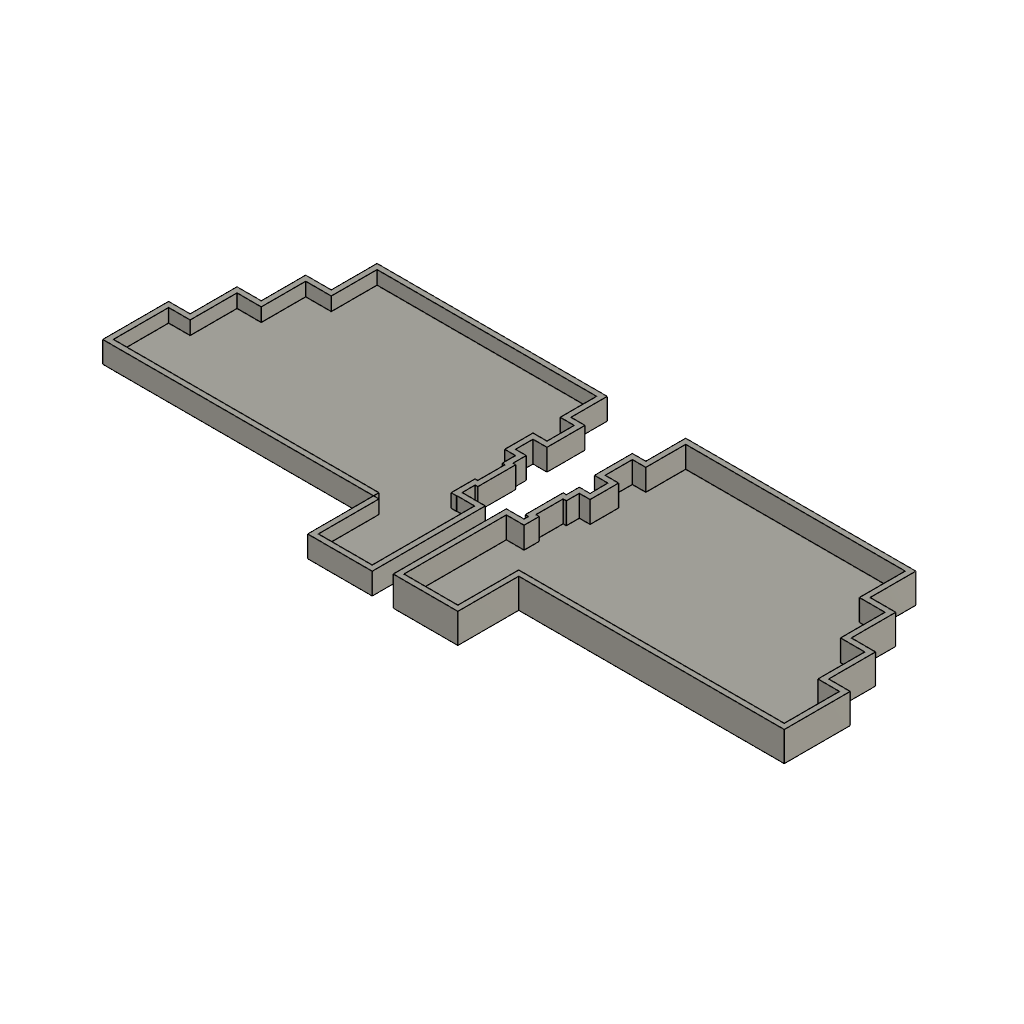
Jarned V2 (Autodesk Fusion 360 design; units mm, degrees)
part number: 2026-11-08-21-23-21-897
Autodesk Fusion 360 part; units mm, degrees
sketch "Sketch1" plane through (0, 0, 0) normal (0, 0, 1) x (1, 0, 0)
  line L0 (0, -12.5) -> (98.6, -12.5)
  line L1 (98.6, -12.5) -> (98.6, 0.9)
  line L2 (98.6, 0.9) -> (100, 0.9)
  line L3 (100, 0.9) -> (100, 2.9)
  line L4 (100, 2.9) -> (112, 2.9)
  line L5 (112, 2.9) -> (112, 9.8)
  line L6 (112, 9.8) -> (113, 9.8)
  line L7 (113, 9.8) -> (113, 19.9)
  line L8 (113, 19.9) -> (112, 19.9)
  line L9 (112, 19.9) -> (112, 24.8)
  line L10 (112, 24.8) -> (108, 24.8)
  line L11 (108, 24.8) -> (108, 35.3)
  line L12 (108, 35.3) -> (113.2, 35.3)
  line L13 (113.2, 35.3) -> (113.2, 45.4)
  line L14 (113.2, 45.4) -> (108, 45.4)
  line L15 (108, 45.4) -> (108, 58.9)
  line L16 (108, 58.9) -> (26.5, 58.9)
  line L17 (26.5, 58.9) -> (26.5, 41.9)
  line L18 (26.5, 41.9) -> (17, 41.9)
  line L19 (17, 41.9) -> (17, 25.4)
  line L20 (17, 25.4) -> (8, 25.4)
  line L21 (8, 25.4) -> (8, 8)
  line L22 (8, 8) -> (0, 8)
  line L23 (0, 8) -> (0, -12.5)
  line L24 (15, 27.4) -> (6, 27.4)
  line L25 (6, 27.4) -> (6, 10)
  line L26 (6, 10) -> (-2, 10)
  line L27 (-2, 10) -> (-2, -14.5)
  line L28 (-2, -14.5) -> (100.6, -14.5)
  line L29 (100.6, -14.5) -> (100.6, -1.1)
  line L30 (100.6, -1.1) -> (102, -1.1)
  line L31 (102, -1.1) -> (102, 0.9)
  line L32 (102, 0.9) -> (114, 0.9)
  line L33 (114, 0.9) -> (114, 7.8)
  line L34 (114, 7.8) -> (115, 7.8)
  line L35 (115, 7.8) -> (115, 21.9)
  line L36 (115, 21.9) -> (114, 21.9)
  line L37 (114, 21.9) -> (114, 26.8)
  line L38 (114, 26.8) -> (110, 26.8)
  line L39 (110, 26.8) -> (110, 33.3)
  line L40 (110, 33.3) -> (115.2, 33.3)
  line L41 (115.2, 33.3) -> (115.2, 47.4)
  line L42 (115.2, 47.4) -> (110, 47.4)
  line L43 (110, 47.4) -> (110, 60.9)
  line L44 (110, 60.9) -> (24.5, 60.9)
  line L45 (24.5, 60.9) -> (24.5, 43.9)
  line L46 (24.5, 43.9) -> (15, 43.9)
  line L47 (15, 43.9) -> (15, 27.4)
  dimension "d1" = 98.6
  dimension "d2" = 13.4
  dimension "d3" = 2
  dimension "d4" = 12
  dimension "d5" = 6.9
  dimension "d6" = 10.1
  dimension "d7" = 4.9
  dimension "d8" = 4
  dimension "d9" = 10.5
  dimension "d10" = 5.2
  dimension "d11" = 10.1
  dimension "d12" = 13.5
  dimension "d13" = 81.5
  dimension "d14" = 17
  dimension "d15" = 9.5
  dimension "d16" = 16.5
  dimension "d17" = 9
  dimension "d18" = 17.4
  dimension "d19" = 2
  constraint horizontal L0
  constraint perpendicular L0 L1
  constraint perpendicular L1 L2
  constraint perpendicular L2 L3
  constraint perpendicular L3 L4
  constraint perpendicular L4 L5
  constraint perpendicular L5 L6
  constraint perpendicular L6 L7
  constraint perpendicular L7 L8
  constraint perpendicular L8 L9
  constraint perpendicular L9 L10
  constraint perpendicular L10 L11
  constraint perpendicular L11 L12
  constraint perpendicular L12 L13
  constraint perpendicular L13 L14
  constraint perpendicular L14 L15
  constraint perpendicular L15 L16
  constraint perpendicular L16 L17
  constraint perpendicular L17 L18
  constraint perpendicular L18 L19
  constraint perpendicular L19 L20
  constraint perpendicular L20 L21
  constraint perpendicular L21 L22
  constraint perpendicular L0 L23
  measures "d1" distance of L0.start L0.end
  measures "d2" distance of L0.end L1.end
  measures "d3" distance of L2.end L3.end
  measures "d4" distance of L3.end L4.end
  measures "d5" distance of L4.end L5.end
  measures "d6" distance of L6.end L7.end
  measures "d7" distance of L8.end L9.end
  measures "d8" distance of L9.end L10.end
  measures "d9" distance of L10.end L11.end
  measures "d10" distance of L11.end L12.end
  measures "d11" distance of L12.end L13.end
  measures "d12" distance of L14.end L15.end
  measures "d13" distance of L15.end L16.end
  measures "d14" distance of L16.end L17.end
  measures "d15" distance of L17.end L18.end
  measures "d16" distance of L18.end L19.end
  measures "d17" distance of L19.end L20.end
  measures "d18" distance of L20.end L21.end
extrude "Extrude1" add sketch "Sketch1" along normal blind 6 makes body 1
sketch "Sketch2" plane through (0, 0, 0) normal (0, 0, 1) x (1, 0, 0)
  line L0 (26.5, 58.9) -> (108, 58.9)
  line L1 (108, 58.9) -> (108, 45.4)
  line L2 (108, 45.4) -> (113.2, 45.4)
  line L3 (113.2, 45.4) -> (113.2, 35.3)
  line L4 (113.2, 35.3) -> (108, 35.3)
  line L5 (108, 35.3) -> (108, 24.8)
  line L6 (108, 24.8) -> (112, 24.8)
  line L7 (112, 24.8) -> (112, 19.9)
  line L8 (112, 19.9) -> (113, 19.9)
  line L9 (113, 19.9) -> (113, 9.8)
  line L10 (113, 9.8) -> (112, 9.8)
  line L11 (112, 9.8) -> (112, 2.9)
  line L12 (112, 2.9) -> (100, 2.9)
  line L13 (100, 2.9) -> (100, 0.9)
  line L14 (100, 0.9) -> (98.6, 0.9)
  line L15 (98.6, 0.9) -> (98.6, -12.5)
  line L16 (98.6, -12.5) -> (0, -12.5)
  line L17 (0, -12.5) -> (0, 8)
  line L18 (0, 8) -> (8, 8)
  line L19 (8, 8) -> (8, 25.4)
  line L20 (8, 25.4) -> (17, 25.4)
  line L21 (17, 25.4) -> (17, 41.9)
  line L22 (17, 41.9) -> (26.5, 41.9)
  line L23 (26.5, 41.9) -> (26.5, 58.9)
  constraint horizontal L0
  constraint perpendicular L0 L1
  constraint perpendicular L1 L2
  constraint perpendicular L2 L3
  constraint perpendicular L3 L4
  constraint perpendicular L4 L5
  constraint perpendicular L5 L6
  constraint perpendicular L6 L7
  constraint perpendicular L7 L8
  constraint perpendicular L8 L9
  constraint perpendicular L9 L10
  constraint perpendicular L10 L11
  constraint perpendicular L11 L12
  constraint perpendicular L12 L13
  constraint perpendicular L13 L14
  constraint perpendicular L12 L15
  constraint perpendicular L13 L16
  constraint perpendicular L12 L17
  constraint perpendicular L17 L18
  constraint perpendicular L18 L19
  constraint perpendicular L19 L20
  constraint perpendicular L20 L21
  constraint perpendicular L21 L22
  constraint perpendicular L0 L23
extrude "Extrude2" add sketch "Sketch2" along normal blind 3 bodies 1
sketch "Sketch3" plane through (0, 0, 0) normal (0, 0, 1) x (1, 0, 0)
  line L0 (140, 60) -> (221.5, 60)
  line L1 (221.5, 60) -> (221.5, 43)
  line L2 (221.5, 43) -> (231, 43)
  line L3 (231, 43) -> (231, 26.5)
  line L4 (231, 26.5) -> (240, 26.5)
  line L5 (240, 26.5) -> (240, 9.1)
  line L6 (240, 9.1) -> (248, 9.1)
  line L7 (248, 9.1) -> (248, -11.4)
  line L8 (248, -11.4) -> (149.4, -11.4)
  line L9 (149.4, -11.4) -> (149.4, 2)
  line L10 (149.4, 2) -> (148, 2)
  line L11 (148, 2) -> (148, 4)
  line L12 (148, 4) -> (136, 4)
  line L13 (136, 4) -> (136, 9.6)
  line L14 (136, 9.6) -> (134.8, 9.6)
  line L15 (134.8, 9.6) -> (134.8, 19.7)
  line L16 (134.8, 19.7) -> (136, 19.7)
  line L17 (136, 19.7) -> (136, 24.5)
  line L18 (136, 24.5) -> (140, 24.5)
  line L19 (140, 24.5) -> (140, 35.1)
  line L20 (140, 35.1) -> (135, 35.1)
  line L21 (135, 35.1) -> (135, 45.2)
  line L22 (135, 45.2) -> (140, 45.2)
  line L23 (140, 45.2) -> (140, 60)
  line L24 (223.5, 45) -> (233, 45)
  line L25 (233, 45) -> (233, 28.5)
  line L26 (233, 28.5) -> (242, 28.5)
  line L27 (242, 28.5) -> (242, 11.1)
  line L28 (242, 11.1) -> (250, 11.1)
  line L29 (250, 11.1) -> (250, -13.4)
  line L30 (250, -13.4) -> (147.4, -13.4)
  line L31 (147.4, -13.4) -> (147.4, 0)
  line L32 (147.4, 0) -> (146, 0)
  line L33 (146, 0) -> (146, 2)
  line L34 (146, 2) -> (134, 2)
  line L35 (134, 2) -> (134, 7.6)
  line L36 (134, 7.6) -> (132.8, 7.6)
  line L37 (132.8, 7.6) -> (132.8, 21.7)
  line L38 (132.8, 21.7) -> (134, 21.7)
  line L39 (134, 21.7) -> (134, 26.5)
  line L40 (134, 26.5) -> (138, 26.5)
  line L41 (138, 26.5) -> (138, 33.1)
  line L42 (138, 33.1) -> (133, 33.1)
  line L43 (133, 33.1) -> (133, 47.2)
  line L44 (133, 47.2) -> (138, 47.2)
  line L45 (138, 47.2) -> (138, 62)
  line L46 (138, 62) -> (223.5, 62)
  line L47 (223.5, 62) -> (223.5, 45)
  dimension "d24" = 81.5
  dimension "d25" = 17
  dimension "d26" = 9.5
  dimension "d27" = 16.5
  dimension "d28" = 9
  dimension "d29" = 17.4
  dimension "d30" = 8
  dimension "d31" = 20.5
  dimension "d32" = 98.6
  dimension "d33" = 13.4
  dimension "d34" = 12
  dimension "d35" = 5.6
  dimension "d36" = 1.2
  dimension "d37" = 10.1
  dimension "d38" = 4.8
  dimension "d39" = 4
  dimension "d40" = 10.6
  dimension "d41" = 5
  dimension "d42" = 10.1
  dimension "d43" = -2
  constraint horizontal L0
  constraint perpendicular L0 L1
  constraint perpendicular L1 L2
  constraint perpendicular L2 L3
  constraint perpendicular L3 L4
  constraint perpendicular L4 L5
  constraint perpendicular L5 L6
  constraint perpendicular L6 L7
  constraint perpendicular L7 L8
  constraint perpendicular L8 L9
  constraint perpendicular L9 L10
  constraint perpendicular L10 L11
  constraint perpendicular L11 L12
  constraint perpendicular L12 L13
  constraint perpendicular L13 L14
  constraint perpendicular L14 L15
  constraint perpendicular L15 L16
  constraint perpendicular L16 L17
  constraint perpendicular L17 L18
  constraint perpendicular L18 L19
  constraint perpendicular L19 L20
  constraint perpendicular L20 L21
  constraint perpendicular L21 L22
  constraint perpendicular L0 L23
  measures "d24" distance of L0.start L0.end
  measures "d25" distance of L0.end L1.end
  measures "d26" distance of L1.end L2.end
  measures "d27" distance of L2.end L3.end
  measures "d28" distance of L3.end L4.end
  measures "d29" distance of L4.end L5.end
  measures "d30" distance of L5.end L6.end
  measures "d31" distance of L6.end L7.end
  measures "d32" distance of L7.end L8.end
  measures "d33" distance of L8.end L9.end
  measures "d34" distance of L11.end L12.end
  measures "d35" distance of L12.end L13.end
  measures "d36" distance of L13.end L14.end
  measures "d37" distance of L14.end L15.end
  measures "d38" distance of L16.end L17.end
  measures "d39" distance of L17.end L18.end
  measures "d40" distance of L18.end L19.end
  measures "d41" distance of L19.end L20.end
  measures "d42" distance of L20.end L21.end
extrude "Extrude3" add sketch "Sketch3" along normal blind 6 separate body makes body 2
extrude "Extrude4" add 1 faces at (32.8667, -13.8333, 6) along direction (0, 0, 1) blind 2 on bodies 1 bodies 1
extrude "Extrude5" add 1 faces at (182.2667, -12.7333, 6) along direction (0, 0, 1) blind 2 on bodies 2 bodies 2
sketch "Sketch4" plane through (0, 0, 0) normal (0, 0, 1) x (1, 0, 0)
  line L0 (140, 60) -> (221.5, 60)
  line L1 (221.5, 60) -> (221.5, 43)
  line L2 (140, 45.216) -> (140, 60)
  line L3 (221.5, 43) -> (231, 43)
  line L4 (231, 43) -> (231, 26.5)
  line L5 (231, 26.5) -> (240, 26.5)
  line L6 (240, 26.5) -> (240, 9.1)
  line L7 (240, 9.1) -> (248, 9.1)
  line L8 (248, 9.1) -> (248, -11.4)
  line L9 (248, -11.4) -> (240, -11.4)
  line L10 (140, 45.216) -> (135, 45.216)
  line L11 (135, 45.216) -> (135, 35.1)
  line L12 (135, 35.1) -> (140, 35.1)
  line L13 (140, 24.5) -> (136, 24.5)
  line L14 (136, 24.5) -> (136, 19.7)
  line L15 (136, 19.7) -> (134.8, 19.7)
  line L16 (134.8, 19.7) -> (134.8, 9.6)
  line L17 (134.8, 9.6) -> (136, 9.6)
  line L18 (148, 4) -> (136, 4)
  line L19 (136, 4) -> (136, 9.6)
  line L20 (149.4, 2) -> (148, 2)
  line L21 (148, 2) -> (148, 4)
  line L22 (240, -11.4) -> (149.4, -11.4)
  line L23 (149.4, -11.4) -> (149.4, 2)
  line L24 (149.4, 2) -> (148, 2)
  line L25 (148, 2) -> (148, 4)
  line L26 (240, 9.6) -> (240, 9.1)
  line L27 (221.5, 43.5352) -> (231, 43.5352)
  line L28 (231, 43.5352) -> (231, 26.5)
  line L29 (140, 24.5) -> (140, 35.1)
  constraint horizontal L0
  constraint vertical L1
  constraint vertical L2
  constraint horizontal L3
  constraint vertical L4
  constraint horizontal L5
  constraint vertical L6
  constraint horizontal L7
  constraint vertical L8
  constraint horizontal L9
  constraint horizontal L10
  constraint vertical L11
  constraint horizontal L12
  constraint horizontal L13
  constraint vertical L14
  constraint horizontal L15
  constraint vertical L16
  constraint horizontal L17
  constraint horizontal L18
  constraint vertical L19
  constraint horizontal L20
  constraint vertical L21
  constraint horizontal L22
  constraint vertical L23
  constraint horizontal L24
  constraint vertical L25
  constraint vertical L26
  constraint vertical L29
  constraint horizontal L27
  constraint vertical L28
  constraint coincident L1 L27.start
extrude "Extrude6" add sketch "Sketch4" against normal blind 3 separate body contours L0 L1 L2 L3 L4 L5 L6 L7 L8 L9 L10 L11 L12 L13 L14 L15 L16 L17 L18 L19 L20 L21 L22 L23 L24 L25 L26 L28 L29 makes body 3
sketch "Sketch5" plane through (0, 0, 0) normal (0, 0, 1) x (1, 0, 0)
sketch "Sketch6" plane through (0, 0, 8) normal (0, 0, 1) x (-1, 0, 0)
  line L0 (0, 12.5) -> (0, -8)
  line L1 (0, -8) -> (-8, -8)
  line L2 (-8, -8) -> (-8, -25.4)
  line L3 (-8, -25.4) -> (-17, -25.4)
  line L4 (-17, -25.4) -> (-17, -41.9)
  line L5 (-17, -41.9) -> (-26.5, -41.9)
  line L6 (-26.5, -41.9) -> (-26.5, -58.9)
  line L7 (-26.5, -58.9) -> (-108, -58.9)
  line L8 (-108, -58.9) -> (-108, -45.4)
  line L9 (-108, -45.4) -> (-113.2, -45.4)
  line L10 (-113.2, -45.4) -> (-113.2, -35.3)
  line L11 (-113.2, -35.3) -> (-108, -35.3)
  line L12 (-108, -35.3) -> (-108, -24.8)
  line L13 (-108, -24.8) -> (-112, -24.8)
  line L14 (-112, -24.8) -> (-112, -19.9)
  line L15 (-112, -19.9) -> (-113, -19.9)
  line L16 (-113, -19.9) -> (-113, -9.8)
  line L17 (-113, -9.8) -> (-112, -9.8)
  line L18 (-112, -9.8) -> (-112, -2.9)
  line L19 (-112, -2.9) -> (-100, -2.9)
  line L20 (-100, -2.9) -> (-100, -0.9)
  line L21 (-100, -0.9) -> (-98.6, -0.9)
  line L22 (-98.6, -0.9) -> (-98.6, 12.5)
  line L23 (-98.6, 12.5) -> (0, 12.5)
  line L24 (-15, -43.9) -> (-15, -27.4)
  line L25 (-15, -27.4) -> (-6, -27.4)
  line L26 (-6, -27.4) -> (-6, -10)
  line L27 (-6, -10) -> (2, -10)
  line L28 (2, -10) -> (2, 14.5)
  line L29 (2, 14.5) -> (-100.6, 14.5)
  line L30 (-100.6, 14.5) -> (-100.6, 1.1)
  line L31 (-100.6, 1.1) -> (-102, 1.1)
  line L32 (-102, 1.1) -> (-102, -0.9)
  line L33 (-102, -0.9) -> (-114, -0.9)
  line L34 (-114, -0.9) -> (-114, -7.8)
  line L35 (-114, -7.8) -> (-115, -7.8)
  line L36 (-115, -7.8) -> (-115, -21.9)
  line L37 (-115, -21.9) -> (-114, -21.9)
  line L38 (-114, -21.9) -> (-114, -26.8)
  line L39 (-114, -26.8) -> (-110, -26.8)
  line L40 (-110, -26.8) -> (-110, -33.3)
  line L41 (-110, -33.3) -> (-115.2, -33.3)
  line L42 (-115.2, -33.3) -> (-115.2, -47.4)
  line L43 (-115.2, -47.4) -> (-110, -47.4)
  line L44 (-110, -47.4) -> (-110, -60.9)
  line L45 (-110, -60.9) -> (-24.5, -60.9)
  line L46 (-24.5, -60.9) -> (-24.5, -43.9)
  line L47 (-24.5, -43.9) -> (-15, -43.9)
  line L48 (-98.6, 12.5) -> (-98.6, 14.5)
  line L49 (-98.6, 14.5) -> (-100.6, 14.5)
  line L50 (-100.6, 14.5) -> (-100.6, 1.1)
  line L51 (-102, 1.1) -> (-100.6, 1.1)
  line L52 (-102, 1.1) -> (-102, -0.9)
  line L53 (-102, -0.9) -> (-112, -0.9)
  line L54 (-112, -2.9) -> (-112, -0.9)
  line L55 (-112, -2.9) -> (-100, -2.9)
  line L56 (-100, -0.9) -> (-100, -2.9)
  line L57 (-100, -0.9) -> (-98.6, -0.9)
  line L58 (-98.6, -0.9) -> (-98.6, 12.5)
  constraint coincident L22.end L23.start
  constraint coincident L29 L48.end
  constraint perpendicular L29 L48
  constraint coincident L29.end L30.start
  constraint coincident L30.end L31.start
  constraint coincident L31.end L32.start
  constraint coincident L32.end L33.start
  constraint coincident L33 L53.end
  constraint coincident L18.end L19.start
  constraint coincident L19.end L20.start
  constraint coincident L20.end L21.start
  constraint coincident L21.end L22.start
extrude "Extrude7" cut sketch "Sketch6" against normal blind 6 contours L19 L20 L21 L22 L29 L30 L31 L32 L33 L48 L49 L50 L51 L52 L53 L54 L55 L56 L57 L58 bodies 1
extrude "Extrude8" add 1 faces at (99.2667, -4.9, 2) along direction (0, 0, 1) blind 1 on bodies 1 bodies 1
sketch "Sketch7" plane through (0, 0, 0) normal (0, 0, 1) x (1, 0, 0)
  line L0 (100.6, -37) -> (120.6, -37)
  line L1 (120.6, -37) -> (120.6, 1)
  line L2 (120.6, 1) -> (112, 1)
  line L3 (100.6, -37) -> (100.6, -14.5)
  line L4 (98.6, -39) -> (98.6, -14.5)
  line L5 (98.6, -39) -> (122.6, -39)
  line L6 (122.6, -39) -> (122.6, 3)
  line L7 (122.6, 3) -> (112, 3)
  line L8 (98.6, -14.5) -> (100.6, -14.5)
  line L9 (112, 3) -> (112, 1)
  dimension "d57" = 20
  dimension "d58" = -2
  constraint perpendicular L0 L1
  constraint perpendicular L1 L2
  constraint perpendicular L0 L3
  constraint perpendicular L3 L8
  constraint perpendicular L2 L9
  measures "d57" distance of L0.start L0.end
extrude "Extrude9" add sketch "Sketch7" along normal blind 8 bodies 1
sketch "Sketch8" plane through (0, 0, 0) normal (0, 0, 1) x (1, 0, 0)
  line L0 (114, 1) -> (114, 0.9)
  line L1 (114, 0.9) -> (102, 0.9)
  line L2 (102, 0.9) -> (102, -1.1)
  line L3 (102, -1.1) -> (100.6, -1.1)
  line L4 (100.6, -1.1) -> (100.6, -37)
  line L5 (100.6, -37) -> (120.6, -37)
  line L6 (120.6, -37) -> (120.6, 1)
  line L7 (120.6, 1) -> (114, 1)
  constraint vertical L0
  constraint perpendicular L0 L1
  constraint perpendicular L1 L2
  constraint perpendicular L2 L3
  constraint perpendicular L3 L4
  constraint perpendicular L4 L5
  constraint perpendicular L3 L6
extrude "Extrude10" add sketch "Sketch8" along normal blind 3 bodies 1
sketch "Sketch9" plane through (0, 0, 8) normal (0, 0, 1) x (-1, 0, 0)
  line L0 (-135, -45.2) -> (-140, -45.2)
  line L1 (-140, -45.2) -> (-140, -60)
  line L2 (-140, -60) -> (-221.5, -60)
  line L3 (-221.5, -60) -> (-221.5, -43)
  line L4 (-221.5, -43) -> (-231, -43)
  line L5 (-231, -43) -> (-231, -26.5)
  line L6 (-231, -26.5) -> (-240, -26.5)
  line L7 (-240, -26.5) -> (-240, -9.1)
  line L8 (-240, -9.1) -> (-248, -9.1)
  line L9 (-248, -9.1) -> (-248, 11.4)
  line L10 (-248, 11.4) -> (-149.4, 11.4)
  line L11 (-149.4, 11.4) -> (-149.4, -2)
  line L12 (-149.4, -2) -> (-148, -2)
  line L13 (-148, -2) -> (-148, -4)
  line L14 (-148, -4) -> (-136, -4)
  line L15 (-136, -4) -> (-136, -9.6)
  line L16 (-136, -9.6) -> (-134.8, -9.6)
  line L17 (-134.8, -9.6) -> (-134.8, -19.7)
  line L18 (-134.8, -19.7) -> (-136, -19.7)
  line L19 (-136, -19.7) -> (-136, -24.5)
  line L20 (-136, -24.5) -> (-140, -24.5)
  line L21 (-140, -24.5) -> (-140, -35.1)
  line L22 (-140, -35.1) -> (-135, -35.1)
  line L23 (-135, -35.1) -> (-135, -45.2)
  line L24 (-223.5, -62) -> (-138, -62)
  line L25 (-138, -62) -> (-138, -47.2)
  line L26 (-138, -47.2) -> (-133, -47.2)
  line L27 (-133, -47.2) -> (-133, -33.1)
  line L28 (-133, -33.1) -> (-138, -33.1)
  line L29 (-138, -33.1) -> (-138, -26.5)
  line L30 (-138, -26.5) -> (-134, -26.5)
  line L31 (-134, -26.5) -> (-134, -21.7)
  line L32 (-134, -21.7) -> (-132.8, -21.7)
  line L33 (-132.8, -21.7) -> (-132.8, -7.6)
  line L34 (-132.8, -7.6) -> (-134, -7.6)
  line L35 (-134, -7.6) -> (-134, -2)
  line L36 (-134, -2) -> (-146, -2)
  line L37 (-146, -2) -> (-146, 0)
  line L38 (-146, 0) -> (-147.4, 0)
  line L39 (-147.4, 0) -> (-147.4, 13.4)
  line L40 (-147.4, 13.4) -> (-250, 13.4)
  line L41 (-250, 13.4) -> (-250, -11.1)
  line L42 (-250, -11.1) -> (-242, -11.1)
  line L43 (-242, -11.1) -> (-242, -28.5)
  line L44 (-242, -28.5) -> (-233, -28.5)
  line L45 (-233, -28.5) -> (-233, -45)
  line L46 (-233, -45) -> (-223.5, -45)
  line L47 (-223.5, -45) -> (-223.5, -62)
  line L48 (-149.4, 11.4) -> (-149.4, 13.4)
  line L49 (-147.4, 13.4) -> (-149.4, 13.4)
  line L50 (-147.4, 13.4) -> (-147.4, 0)
  line L51 (-146, 0) -> (-147.4, 0)
  line L52 (-146, 0) -> (-146, -2)
  line L53 (-134, -4) -> (-136, -4)
  line L54 (-136, -4) -> (-148, -4)
  line L55 (-148, -2) -> (-148, -4)
  line L56 (-148, -2) -> (-149.4, -2)
  line L57 (-149.4, -2) -> (-149.4, 11.4)
  line L58 (-134, -4) -> (-134, -2)
  line L59 (-134, -2) -> (-146, -2)
  constraint coincident L10.end L11.start
  constraint coincident L40 L48.end
  constraint perpendicular L40 L48
  constraint coincident L39.end L40.start
  constraint coincident L38.end L39.start
  constraint coincident L37.end L38.start
  constraint coincident L36.end L37.start
  constraint coincident L35 L53.start
  constraint coincident L14.end L15.start
  constraint perpendicular L15 L53
  constraint coincident L13.end L14.start
  constraint coincident L12.end L13.start
  constraint coincident L11.end L12.start
  constraint coincident L35.end L36.start
extrude "Extrude11" cut sketch "Sketch9" against normal blind 11 contours L11 L12 L13 L14 L35 L36 L37 L38 L39 L40 L48 L49 L50 L51 L52 L53 L54 L55 L56 L57 L58 L59 bodies 2
extrude "Extrude12" add 1 faces at (215.8, -12.7333, 0) along direction (0, 0, -1) blind 3 on bodies 2 bodies 2 3
sketch "Sketch10" plane through (0, 0, 0) normal (0, 0, 1) x (1, 0, 0)
  line L0 (149.4, 4) -> (129.4, 4)
  line L1 (149.4, 4) -> (149.4, -34)
  line L2 (129.4, 4) -> (129.4, -34)
  line L3 (129.4, -34) -> (149.4, -34)
  dimension "d67" = 20
  dimension "d68" = 38
  constraint perpendicular L0 L1
  constraint perpendicular L0 L2
  measures "d67" distance of L0.start L0.end
  measures "d68" distance of L0.start L1.end
extrude "Extrude13" add sketch "Sketch10" along normal blind 3 bodies 2
extrude "Extrude14" add 1 faces at (136.0667, -14.4667, 0) along direction (0, 0, -1) blind 3 on bodies 2 bodies 2
extrude "Extrude15" cut 1 faces at (136.0667, -14.4667, 3) along direction (0, 0, -1) blind 3 on bodies 2 bodies 2
sketch "Sketch11" plane through (0, 0, 0) normal (0, 1, 0) x (1, 0, 0)
sketch "Sketch12" plane through (0, 0, 0) normal (0, 0, 1) x (1, 0, 0)
  line L0 (134, 4) -> (129.4, 4)
  line L1 (129.4, 4) -> (129.4, -34)
  line L2 (129.4, -34) -> (149.4, -34)
  line L3 (149.4, -34) -> (149.4, -13.4)
  line L4 (134, 6) -> (127.4, 6)
  line L5 (127.4, 6) -> (127.4, -36)
  line L6 (127.4, -36) -> (151.4, -36)
  line L7 (151.4, -36) -> (151.4, -13.4)
  line L8 (149.4, -13.4) -> (151.4, -13.4)
  line L9 (134, 6) -> (134, 4)
  dimension "d75" = 2
  constraint horizontal L0
  constraint perpendicular L0 L1
  constraint perpendicular L1 L2
  constraint perpendicular L2 L3
  constraint perpendicular L7 L8
  constraint perpendicular L0 L9
extrude "Extrude16" add sketch "Sketch12" along normal blind 8 bodies 2
extrude "Extrude17" add 1 faces at (128.0667, -21.3333, 0) along direction (0, 0, -1) blind 3 on bodies 2 bodies 2
